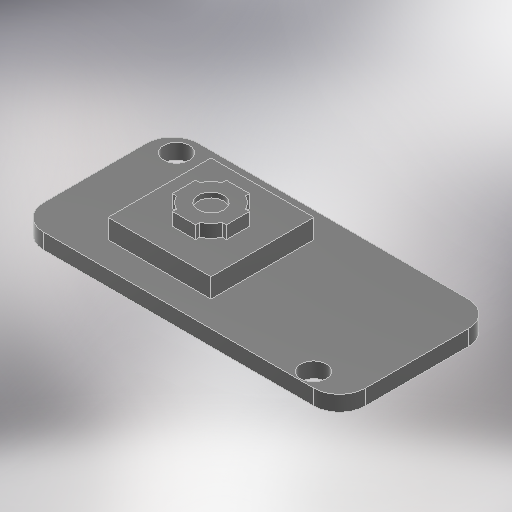
# Autodesk Inventor part: IR_camera
Saved by Autodesk Inventor 2025.3 (Build 293356030, 356C)
## iProperties
Created: 2026-05-07
Part Number: IR_camera
Material: 一般
Document SubType Name: Modeling
Designer: ibuki_ono
Density: 1 g/cm^3
Appearance: 滑らか - 黒
Author: ibuki_ono
Autodesk Inventor part; units mm, degrees
ref_plane "YZ Plane" through (0, 0, 0) normal (1, 0, 0) x (0, 1, 0)
ref_plane "XZ Plane" through (0, 0, 0) normal (0, 1, 0) x (-1, 0, 0)
ref_plane "XY Plane" through (0, 0, 0) normal (0, 0, 1) x (1, 0, 0)
sketch "スケッチ1" plane through (0, 0, 0) normal (0, 1, 0) x (-1, 0, 0)
  line L0 (-16, 6) -> (9, 6)
  line L1 (9, 6) -> (9, -6)
  line L2 (9, -6) -> (-16, -6)
  line L3 (-16, -6) -> (-16, 6)
  line L4 (-16, 6) -> (9, -6) construction
  line L5 (9, 6) -> (-16, -6) construction
  point P0 (0, 0)
  point P1 (-3.5, 0)
  dimension "d0" = 25
  dimension "d1" = 12
  dimension "d2" = 16
  constraints: 12 end point, 2 midpoint, 2 parallel, 1 horizontal, 1 horizontal alignment, 1 perpendicular
  measures "d0" distance of L1.end L2.end
  measures "d1" distance of L0.end L1.end
  measures "d2" distance from line of L3 point (0, 0)
extrude "押し出し1" add sketch "スケッチ1" along normal blind 1.2
sketch "スケッチ2" plane through (0, 1.2, 0) normal (0, 1, 0) x (1, 0, 0)
  line L0 (16, -6) -> (16, 6) projected
  line L1 (16, 6) -> (-9, 6) projected
  line L2 (-9, -6) -> (16, -6) projected
  line L3 (-9, 6) -> (-9, -6) projected
  point P0 (0, 0)
  point P1 (12.85, -4.88)
  point P2 (-7.19, 4.51)
  dimension "d5" = 3.15
  dimension "d8" = 1.81
  dimension "d16" = 1.12
  dimension "d17" = 1.49
  measures "d5" distance from line of L0 point (12.85, -4.88)
  measures "d8" distance from line of L3 point (-7.19, 4.51)
  measures "d16" distance from line of L2 point (12.85, -4.88)
  measures "d17" distance from line of L1 point (-7.19, 4.51)
hole "穴1" at (12.85, 1.2, 4.88) at (-7.19, 1.2, -4.51) direction (0, -1, 0) diameter 2 end through all
sketch "スケッチ3" plane through (0, 1.2, 0) normal (0, 1, 0) x (1, 0, 0)
  line L0 (4, -4) -> (-4, -4)
  line L1 (-4, -4) -> (-4, 4)
  line L2 (-4, 4) -> (4, 4)
  line L3 (4, 4) -> (4, -4)
  line L4 (4, -4) -> (-4, 4) construction
  line L5 (-4, -4) -> (4, 4) construction
  point P0 (0, 0)
  dimension "d18" = 8
  dimension "d19" = 8
  constraints: 12 end point, 2 midpoint, 2 parallel, 1 horizontal, 1 perpendicular
  measures "d18" distance of L1.end L2.end
  measures "d19" distance of L0.end L1.end
extrude "押し出し2" add sketch "スケッチ3" along normal blind 1.5
sketch "スケッチ4" plane through (0, 2.7, 0) normal (0, 1, 0) x (1, 0, 0)
  circle A0 centre (0, 0) radius 2
  line L0 (0.9, -2.1) -> (-0.9, -2.1)
  line L1 (-0.9, -2.1) -> (-0.9, 2.1)
  line L2 (-0.9, 2.1) -> (0.9, 2.1)
  line L3 (0.9, 2.1) -> (0.9, -2.1)
  line L4 (0.9, -2.1) -> (-0.9, 2.1) construction
  line L5 (-0.9, -2.1) -> (0.9, 2.1) construction
  line L6 (2.1, 0.9) -> (-2.1, 0.9)
  line L7 (-2.1, 0.9) -> (-2.1, -0.9)
  line L8 (-2.1, -0.9) -> (2.1, -0.9)
  line L9 (2.1, -0.9) -> (2.1, 0.9)
  line L10 (2.1, 0.9) -> (-2.1, -0.9) construction
  line L11 (-2.1, 0.9) -> (2.1, -0.9) construction
  point P0 (1.7861, 0.9)
  point P1 (0.9, 1.7861)
  point P2 (-0.9, 1.7861)
  point P3 (-1.7861, 0.9)
  point P4 (-1.7861, -0.9)
  point P5 (-0.9, -1.7861)
  point P6 (0.9, -1.7861)
  point P7 (1.7861, -0.9)
  dimension "d22" = 4
  dimension "d23" = 1.8
  dimension "d24" = 4.2
  dimension "d25" = 4.2
  dimension "d26" = 1.8
  constraints: 24 end point, 4 midpoint, 4 parallel, 2 horizontal, 2 perpendicular, 1 centre point, 1 coincident
  measures "d22" diameter of A0
  measures "d23" distance of L1.end L2.end
  measures "d24" distance of L0.end L1.end
  measures "d25" distance of L8.end L7.end
  measures "d26" distance of L7.end L6.end
extrude "押し出し3" add sketch "スケッチ4" along normal blind 1
sketch "スケッチ5" plane through (0, 3.7, 0) normal (0, 1, 0) x (1, 0, 0)
  circle A0 centre (0, 0) radius 1
  dimension "d29" = 2
  constraints: 1 centre point, 1 coincident
  measures "d29" diameter of A0
extrude "押し出し4" cut sketch "スケッチ5" against normal blind 0.4
fillet "フィレット1" radius 2 4 edges at (16, 0.6, 6) (-9, 0.6, 6) (-9, 0.6, -6) (16, 0.6, -6)
equation "\"d25\" = d24"
equation "\"d26\" = d23"
